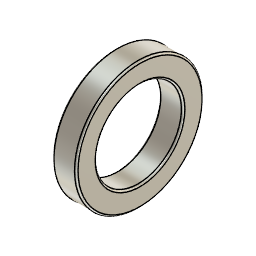
bearing_v4 (Autodesk Fusion 360 design; units mm, degrees)
part number: 2026-11-04-21-39-16-252
Autodesk Fusion 360 part; units mm, degrees
note: some values were not read from the file. Set by a fixed rule: which face or edge a step refers to.
sketch "Sketch1" plane through (0, 0, 0) normal (1, 0, 0) x (0, 1, 0)
  circle A0 centre (0, 0) radius 12.5
  circle A1 centre (0, 0) radius 18.5
  dimension "d1" = 25
  dimension "d2" = 37
  constraint coincident A0.centre A1.centre
  constraint concentric A0 A1
  measures "d1" diameter of A0
  measures "d2" diameter of A1
extrude "Extrude1" add sketch "Sketch1" along normal mid plane 7
fillet "Fillet1" radius 0.5 1 faces at (2.3333, 18.4081, -1.842)
fillet "Fillet2" radius 0.5 1 faces at (2.3333, 12.4379, -1.2446)
